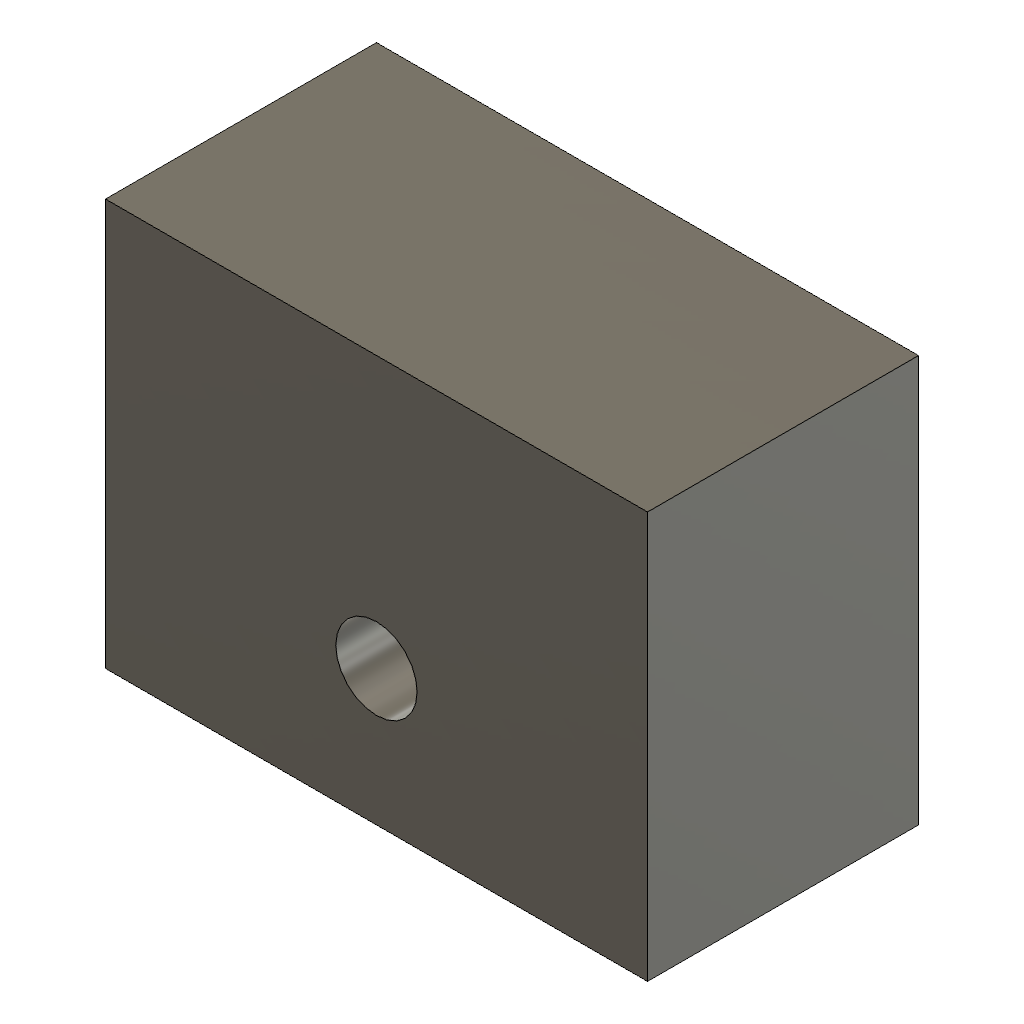
to_bottom (Autodesk Fusion 360 design; units mm, degrees)
part number: 2026-10-20-19-09-11-873
Autodesk Fusion 360 part; units mm, degrees
sketch "BlockProfile" plane through (0, 0, 0) normal (0, 0, 1) x (1, 0, 0)
  line L0 (10, 10) -> (50, 10)
  line L1 (50, 10) -> (50, 40)
  line L2 (50, 40) -> (10, 40)
  line L3 (10, 40) -> (10, 10)
extrude "BlockExtrusion" add sketch "BlockProfile" along normal blind 20
hole "ProbeHole" at (30, 20, 20) direction (0, 0, -1) diameter 6 end up to surface (20 mm away)
